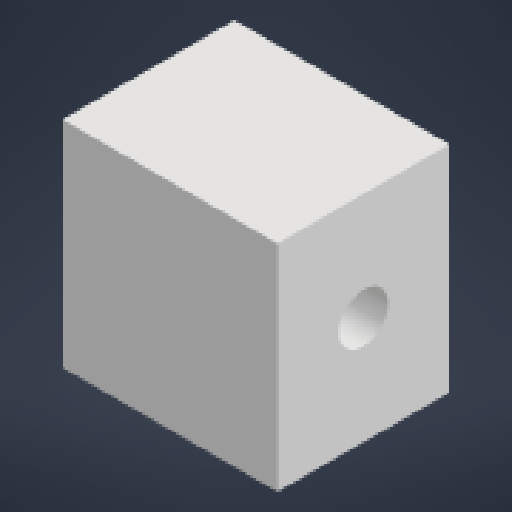
# Autodesk Inventor part: Goi Do Dai Oc
Saved by Autodesk Inventor 2027 (Build 310192060, 192F)
## iProperties
Created: 2026-07-06
Part Number: Goi Do Dai Oc
Material: Generic
Document SubType Name: Modeling
Designer: Laptop
Density: 1 g/cm^3
Appearance: Default
Author: Laptop
Autodesk Inventor part; units mm, degrees
ref_plane "YZ Plane" through (0, 0, 0) normal (1, 0, 0) x (0, 1, 0)
ref_plane "XZ Plane" through (0, 0, 0) normal (0, 1, 0) x (-1, 0, 0)
ref_plane "XY Plane" through (0, 0, 0) normal (0, 0, 1) x (1, 0, 0)
sketch "Sketch1" plane through (0, 0, 0) normal (0, 1, 0) x (-1, 0, 0)
  line L0 (0, 0) -> (-35.0012, 0)
  line L1 (-35.0012, 0) -> (-35.0012, -28.001)
  line L2 (-35.0012, -28.001) -> (0, -28.001)
  line L3 (0, -28.001) -> (0, 0)
  dimension "d0" = 35.0012
  dimension "d1" = 28.001
  constraints: 8 end point, 2 parallel, 1 horizontal, 1 perpendicular
  measures "d0" distance of L2.end L1.end
  measures "d1" distance of L0.end L1.end
extrude "Extrusion1" add sketch "Sketch1" along normal blind 35.0012
sketch "Sketch2" plane through (35.0012, 0, 0) normal (1, 0, 0) x (0, 0, -1)
  line L0 (0, 35.0012) -> (28.001, 35.0012) projected
  line L1 (0, 0) -> (28.001, 0) projected
  circle A0 centre (14.0005, 17.5006) radius 4
  dimension "d4" = 8
  constraints: 1 centre point
  measures "d4" diameter of A0
extrude "Extrusion2" cut sketch "Sketch2" against normal blind 127
body "Solid1"
